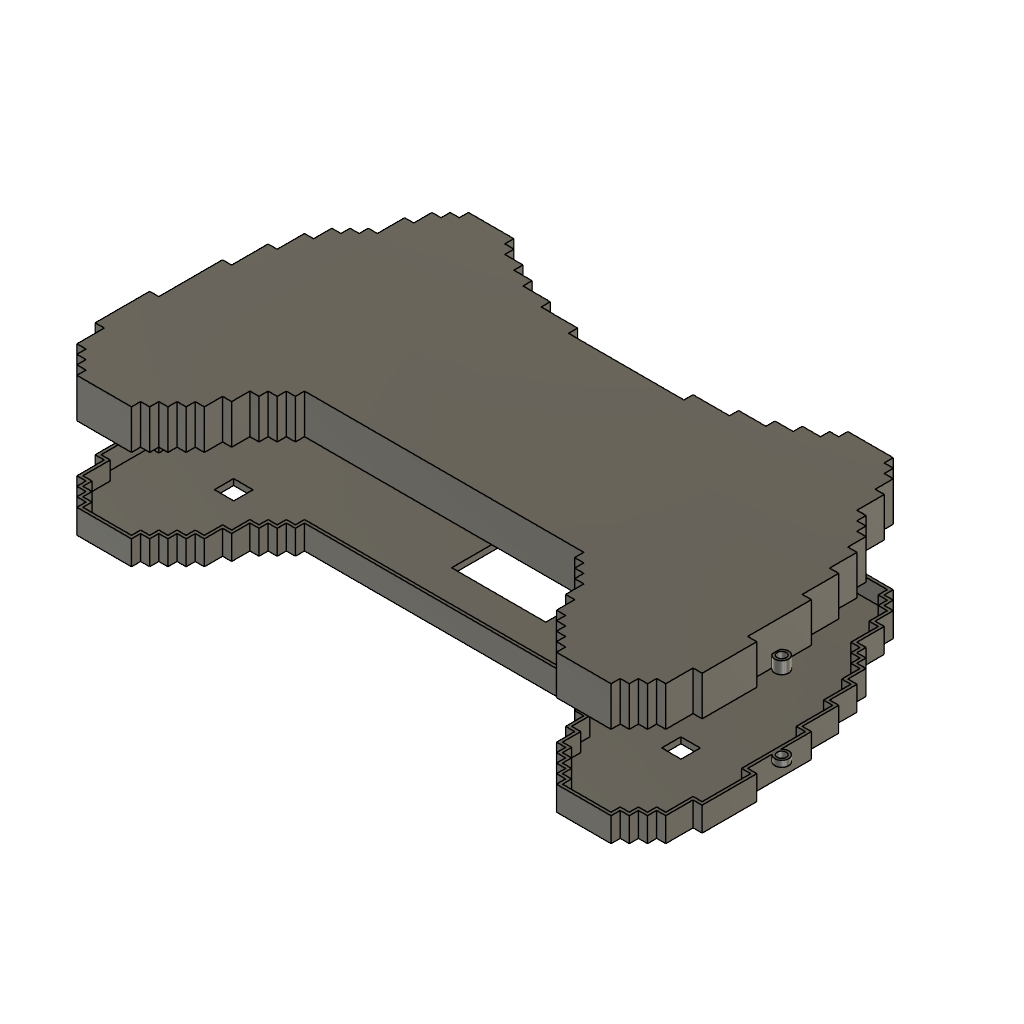
SnapPixel controller (Autodesk Fusion 360 design; units mm, degrees)
part number: 2026-10-10-15-33-20-535
Autodesk Fusion 360 part; units mm, degrees
(part 1 of 3)
sketch "Sketch1" plane through (0, 0, 0) normal (0, 0, 1) x (1, 0, 0)
sketch "Sketch2" plane through (0, 0, 0) normal (0, 0, 1) x (1, 0, 0)
  line L0 (375, 300) -> (406, 300)
  line L1 (406, 300) -> (406, 270.5)
  line L2 (406, 270.5) -> (375, 270.5)
  line L3 (375, 270.5) -> (375, 300)
  line L4 (391, 310) -> (406, 310)
  line L5 (406, 310) -> (409, 310)
  line L6 (409, 310) -> (409, 313)
  line L7 (406, 313) -> (406, 310)
  line L8 (403, 313) -> (403, 310)
  line L9 (400, 313) -> (400, 310)
  line L10 (397, 313) -> (397, 310)
  line L11 (394, 313) -> (394, 310)
  line L12 (391, 313) -> (391, 310)
  line L13 (409, 313) -> (412, 313)
  line L14 (412, 313) -> (412, 316)
  line L15 (412, 316) -> (409, 316)
  line L16 (409, 316) -> (409, 313)
  line L17 (412, 316) -> (415, 316)
  line L18 (415, 316) -> (415, 313)
  line L19 (415, 313) -> (412, 313)
  line L20 (412, 313) -> (412, 316)
  line L21 (415, 316) -> (418, 316)
  line L22 (418, 316) -> (418, 313)
  line L23 (418, 313) -> (415, 313)
  line L24 (415, 313) -> (415, 316)
  line L25 (418, 316) -> (421, 316)
  line L26 (421, 316) -> (421, 313)
  line L27 (421, 313) -> (418, 313)
  line L28 (418, 313) -> (418, 316)
  line L29 (421, 316) -> (424, 316)
  line L30 (424, 316) -> (424, 313)
  line L31 (424, 313) -> (421, 313)
  line L32 (421, 313) -> (421, 316)
  line L33 (421, 316) -> (424, 316)
  line L34 (424, 316) -> (424, 319)
  line L35 (424, 319) -> (421, 319)
  line L36 (421, 319) -> (421, 316)
  line L37 (424, 319) -> (427, 319)
  line L38 (427, 319) -> (427, 316)
  line L39 (427, 316) -> (424, 316)
  line L40 (424, 316) -> (424, 319)
  line L41 (427, 319) -> (430, 319)
  line L42 (430, 319) -> (430, 316)
  line L43 (430, 316) -> (427, 316)
  line L44 (427, 316) -> (427, 319)
  line L45 (430, 319) -> (433, 319)
  line L46 (433, 319) -> (433, 322)
  line L47 (433, 322) -> (430, 322)
  line L48 (430, 322) -> (430, 319)
  line L49 (433, 322) -> (436, 322)
  line L50 (436, 322) -> (436, 319)
  line L51 (436, 319) -> (433, 319)
  line L52 (433, 319) -> (433, 322)
  line L53 (436, 322) -> (439, 322)
  line L54 (439, 322) -> (439, 325)
  line L55 (439, 325) -> (436, 325)
  line L56 (436, 325) -> (436, 322)
  line L57 (439, 325) -> (442, 325)
  line L58 (442, 325) -> (442, 322)
  line L59 (442, 322) -> (439, 322)
  line L60 (439, 322) -> (439, 325)
  line L61 (442, 325) -> (445, 325)
  line L62 (445, 325) -> (445, 328)
  line L63 (445, 328) -> (442, 328)
  line L64 (442, 328) -> (442, 325)
  line L65 (445, 328) -> (448, 328)
  line L66 (448, 328) -> (448, 331)
  line L67 (448, 331) -> (445, 331)
  line L68 (445, 331) -> (445, 328)
  line L69 (445, 325) -> (448, 325)
  line L70 (448, 325) -> (448, 322)
  line L71 (448, 322) -> (445, 322)
  line L72 (445, 322) -> (445, 325)
  line L73 (445, 328) -> (448, 328)
  line L74 (448, 328) -> (448, 325)
  line L75 (448, 325) -> (445, 325)
  line L76 (445, 325) -> (445, 328)
  line L77 (448, 331) -> (451, 331)
  line L78 (451, 331) -> (451, 328)
  line L79 (451, 328) -> (448, 328)
  line L80 (448, 328) -> (448, 331)
  line L81 (451, 331) -> (454, 331)
  line L82 (454, 331) -> (454, 328)
  line L83 (454, 328) -> (451, 328)
  line L84 (451, 328) -> (451, 331)
  line L85 (454, 331) -> (457, 331)
  line L86 (457, 331) -> (457, 328)
  line L87 (457, 328) -> (454, 328)
  line L88 (454, 328) -> (454, 331)
  line L89 (457, 331) -> (460, 331)
  line L90 (460, 331) -> (460, 328)
  line L91 (460, 328) -> (457, 328)
  line L92 (457, 328) -> (457, 331)
  line L93 (448, 328) -> (451, 328)
  line L94 (451, 328) -> (451, 325)
  line L95 (451, 325) -> (448, 325)
  line L96 (448, 325) -> (448, 328)
  line L97 (451, 328) -> (454, 328)
  line L98 (454, 328) -> (454, 325)
  line L99 (454, 325) -> (451, 325)
  line L100 (451, 325) -> (451, 328)
  line L101 (454, 328) -> (457, 328)
  line L102 (457, 328) -> (457, 325)
  line L103 (457, 325) -> (454, 325)
  line L104 (454, 325) -> (454, 328)
  line L105 (448, 325) -> (451, 325)
  line L106 (451, 325) -> (451, 322)
  line L107 (451, 322) -> (448, 322)
  line L108 (448, 322) -> (448, 325)
  line L109 (451, 325) -> (454, 325)
  line L110 (454, 325) -> (454, 322)
  line L111 (454, 322) -> (451, 322)
  line L112 (451, 322) -> (451, 325)
  line L113 (454, 325) -> (457, 325)
  line L114 (457, 325) -> (457, 322)
  line L115 (457, 322) -> (454, 322)
  line L116 (454, 322) -> (454, 325)
  line L117 (457, 328) -> (460, 328)
  line L118 (460, 328) -> (460, 325)
  line L119 (460, 325) -> (457, 325)
  line L120 (457, 325) -> (457, 328)
  line L121 (457, 325) -> (460, 325)
  line L122 (460, 325) -> (460, 322)
  line L123 (460, 322) -> (457, 322)
  line L124 (457, 322) -> (457, 325)
  line L125 (460, 328) -> (463, 328)
  line L126 (463, 328) -> (463, 325)
  line L127 (463, 325) -> (460, 325)
  line L128 (460, 325) -> (460, 328)
  line L129 (463, 325) -> (466, 325)
  line L130 (466, 325) -> (466, 322)
  line L131 (466, 322) -> (463, 322)
  line L132 (463, 322) -> (463, 325)
  line L133 (463, 322) -> (466, 322)
  line L134 (466, 322) -> (466, 319)
  line L135 (466, 319) -> (463, 319)
  line L136 (463, 319) -> (463, 322)
  line L137 (466, 319) -> (469, 319)
  line L138 (469, 319) -> (469, 316)
  line L139 (469, 316) -> (466, 316)
  line L140 (466, 316) -> (466, 319)
  line L141 (466, 316) -> (469, 316)
  line L142 (469, 316) -> (469, 313)
  line L143 (469, 313) -> (466, 313)
  line L144 (466, 313) -> (466, 316)
  line L145 (466, 313) -> (469, 313)
  line L146 (469, 313) -> (469, 310)
  line L147 (469, 310) -> (466, 310)
  line L148 (466, 310) -> (466, 313)
  line L149 (469, 310) -> (472, 310)
  line L150 (472, 310) -> (472, 307)
  line L151 (472, 307) -> (469, 307)
  line L152 (469, 307) -> (469, 310)
  line L153 (472, 307) -> (475, 307)
  line L154 (475, 307) -> (475, 304)
  line L155 (475, 304) -> (472, 304)
  line L156 (472, 304) -> (472, 307)
  line L157 (475, 304) -> (478, 304)
  line L158 (478, 304) -> (478, 301)
  line L159 (478, 301) -> (475, 301)
  line L160 (475, 301) -> (475, 304)
  line L161 (475, 301) -> (478, 301)
  line L162 (478, 301) -> (478, 298)
  line L163 (478, 298) -> (475, 298)
  line L164 (475, 298) -> (475, 301)
  line L165 (478, 298) -> (481, 298)
  line L166 (481, 298) -> (481, 295)
  line L167 (481, 295) -> (478, 295)
  line L168 (478, 295) -> (478, 298)
  line L169 (478, 295) -> (481, 295)
  line L170 (481, 295) -> (481, 292)
  line L171 (481, 292) -> (478, 292)
  line L172 (478, 292) -> (478, 295)
  line L173 (478, 292) -> (481, 292)
  line L174 (481, 292) -> (481, 289)
  line L175 (481, 289) -> (478, 289)
  line L176 (478, 289) -> (478, 292)
  line L177 (481, 289) -> (484, 289)
  line L178 (484, 289) -> (484, 286)
  line L179 (484, 286) -> (481, 286)
  line L180 (481, 286) -> (481, 289)
  line L181 (481, 286) -> (484, 286)
  line L182 (484, 286) -> (484, 283)
  line L183 (484, 283) -> (481, 283)
  line L184 (481, 283) -> (481, 286)
  line L185 (481, 283) -> (484, 283)
  line L186 (484, 283) -> (484, 280)
  line L187 (484, 280) -> (481, 280)
  line L188 (481, 280) -> (481, 283)
  line L189 (481, 280) -> (484, 280)
  line L190 (484, 280) -> (484, 277)
  line L191 (484, 277) -> (481, 277)
  line L192 (481, 277) -> (481, 280)
  line L193 (481, 277) -> (484, 277)
  line L194 (484, 277) -> (484, 274)
  line L195 (484, 274) -> (481, 274)
  line L196 (481, 274) -> (481, 277)
  line L197 (484, 277) -> (487, 277)
  line L198 (487, 277) -> (487, 274)
  line L199 (487, 274) -> (484, 274)
  line L200 (484, 274) -> (484, 277)
  line L201 (484, 274) -> (487, 274)
  line L202 (487, 274) -> (487, 271)
  line L203 (487, 271) -> (484, 271)
  line L204 (484, 271) -> (484, 274)
  line L205 (484, 271) -> (487, 271)
  line L206 (487, 271) -> (487, 268)
  line L207 (487, 268) -> (484, 268)
  line L208 (484, 268) -> (484, 271)
  line L209 (484, 268) -> (487, 268)
  line L210 (487, 268) -> (487, 265)
  line L211 (487, 265) -> (484, 265)
  line L212 (484, 265) -> (484, 268)
  line L213 (484, 265) -> (487, 265)
  line L214 (487, 265) -> (487, 262)
  line L215 (487, 262) -> (484, 262)
  line L216 (484, 262) -> (484, 265)
  line L217 (484, 262) -> (487, 262)
  line L218 (487, 262) -> (487, 259)
  line L219 (487, 259) -> (484, 259)
  line L220 (484, 259) -> (484, 262)
  line L221 (484, 259) -> (487, 259)
  line L222 (487, 259) -> (487, 256)
  line L223 (487, 256) -> (484, 256)
  line L224 (484, 256) -> (484, 259)
  line L225 (484, 256) -> (487, 256)
  line L226 (487, 256) -> (487, 253)
  line L227 (487, 253) -> (484, 253)
  line L228 (484, 253) -> (484, 256)
  line L229 (487, 256) -> (490, 256)
  line L230 (490, 256) -> (490, 253)
  line L231 (490, 253) -> (487, 253)
  line L232 (487, 253) -> (487, 256)
  line L233 (487, 253) -> (490, 253)
  line L234 (490, 253) -> (490, 250)
  line L235 (490, 250) -> (487, 250)
  line L236 (487, 250) -> (487, 253)
  line L237 (487, 250) -> (490, 250)
  line L238 (490, 250) -> (490, 247)
  line L239 (490, 247) -> (487, 247)
  line L240 (487, 247) -> (487, 250)
  line L241 (487, 247) -> (490, 247)
  line L242 (490, 247) -> (490, 244)
  line L243 (490, 244) -> (487, 244)
  line L244 (487, 244) -> (487, 247)
  line L245 (487, 244) -> (490, 244)
  line L246 (490, 244) -> (490, 241)
  line L247 (490, 241) -> (487, 241)
  line L248 (487, 241) -> (487, 244)
  line L249 (487, 241) -> (490, 241)
  line L250 (490, 241) -> (490, 238)
  line L251 (490, 238) -> (487, 238)
  line L252 (487, 238) -> (487, 241)
  line L253 (487, 238) -> (484, 238)
  line L254 (484, 238) -> (484, 241)
  line L255 (484, 241) -> (487, 241)
  line L256 (487, 241) -> (487, 238)
  line L257 (484, 238) -> (487, 238)
  line L258 (487, 238) -> (487, 235)
  line L259 (487, 235) -> (484, 235)
  line L260 (484, 235) -> (484, 238)
  line L261 (484, 235) -> (487, 235)
  line L262 (487, 235) -> (487, 232)
  line L263 (487, 232) -> (484, 232)
  line L264 (484, 232) -> (484, 235)
  line L265 (484, 232) -> (487, 232)
  line L266 (487, 232) -> (487, 229)
  line L267 (487, 229) -> (484, 229)
  line L268 (484, 229) -> (484, 232)
  line L269 (484, 232) -> (481, 232)
  line L270 (481, 232) -> (481, 229)
  line L271 (481, 229) -> (484, 229)
  line L272 (484, 229) -> (484, 232)
  line L273 (481, 229) -> (484, 229)
  line L274 (484, 229) -> (484, 226)
  line L275 (484, 226) -> (481, 226)
  line L276 (481, 226) -> (481, 229)
  line L277 (478, 229) -> (481, 229)
  line L278 (481, 229) -> (481, 226)
  line L279 (481, 226) -> (478, 226)
  line L280 (478, 226) -> (478, 229)
  line L281 (478, 226) -> (481, 226)
  line L282 (481, 226) -> (481, 223)
  line L283 (481, 223) -> (478, 223)
  line L284 (478, 223) -> (478, 226)
  line L285 (478, 223) -> (475, 223)
  line L286 (475, 223) -> (475, 220)
  line L287 (475, 220) -> (478, 220)
  line L288 (478, 220) -> (478, 223)
  line L289 (475, 223) -> (472, 223)
  line L290 (472, 223) -> (472, 220)
  line L291 (472, 220) -> (475, 220)
  line L292 (475, 220) -> (475, 223)
  line L293 (472, 223) -> (469, 223)
  line L294 (469, 223) -> (469, 220)
  line L295 (469, 220) -> (472, 220)
  line L296 (472, 220) -> (472, 223)
  line L297 (469, 223) -> (466, 223)
  line L298 (466, 223) -> (466, 220)
  line L299 (466, 220) -> (469, 220)
  line L300 (469, 220) -> (469, 223)
  line L301 (466, 223) -> (463, 223)
  line L302 (463, 223) -> (463, 220)
  line L303 (463, 220) -> (466, 220)
  line L304 (466, 220) -> (466, 223)
  line L305 (463, 223) -> (460, 223)
  line L306 (460, 223) -> (460, 220)
  line L307 (460, 220) -> (463, 220)
  line L308 (463, 220) -> (463, 223)
  line L309 (460, 226) -> (463, 226)
  line L310 (463, 226) -> (463, 223)
  line L311 (463, 223) -> (460, 223)
  line L312 (460, 223) -> (460, 226)
  line L313 (460, 226) -> (457, 226)
  line L314 (457, 226) -> (457, 223)
  line L315 (457, 223) -> (460, 223)
  line L316 (460, 223) -> (460, 226)
  line L317 (457, 226) -> (454, 226)
  line L318 (454, 226) -> (454, 229)
  line L319 (454, 229) -> (457, 229)
  line L320 (457, 229) -> (457, 226)
  line L321 (454, 229) -> (451, 229)
  line L322 (451, 229) -> (451, 232)
  line L323 (451, 232) -> (454, 232)
  line L324 (454, 232) -> (454, 229)
  line L325 (451, 232) -> (454, 232)
  line L326 (454, 232) -> (454, 235)
  line L327 (454, 235) -> (451, 235)
  line L328 (451, 235) -> (451, 232)
  line L329 (451, 235) -> (448, 235)
  line L330 (448, 235) -> (448, 232)
  line L331 (448, 232) -> (451, 232)
  line L332 (451, 232) -> (451, 235)
  line L333 (448, 235) -> (451, 235)
  line L334 (451, 235) -> (451, 238)
  line L335 (451, 238) -> (448, 238)
  line L336 (448, 238) -> (448, 235)
  line L337 (448, 238) -> (445, 238)
  line L338 (445, 238) -> (445, 241)
  line L339 (445, 241) -> (448, 241)
  line L340 (448, 241) -> (448, 238)
  line L341 (448, 241) -> (445, 241)
  line L342 (445, 241) -> (445, 244)
  line L343 (445, 244) -> (448, 244)
  line L344 (448, 244) -> (448, 241)
  line L345 (448, 244) -> (445, 244)
  line L346 (445, 244) -> (445, 247)
  line L347 (445, 247) -> (448, 247)
  line L348 (448, 247) -> (448, 244)
  line L349 (445, 247) -> (442, 247)
  line L350 (442, 247) -> (442, 244)
  line L351 (442, 244) -> (445, 244)
  line L352 (445, 244) -> (445, 247)
  line L353 (445, 247) -> (442, 247)
  line L354 (442, 247) -> (442, 250)
  line L355 (442, 250) -> (445, 250)
  line L356 (445, 250) -> (445, 247)
  line L357 (442, 250) -> (439, 250)
  line L358 (439, 250) -> (439, 247)
  line L359 (439, 247) -> (442, 247)
  line L360 (442, 247) -> (442, 250)
  line L361 (439, 250) -> (436, 250)
  line L362 (436, 250) -> (436, 253)
  line L363 (436, 253) -> (439, 253)
  line L364 (439, 253) -> (439, 250)
  line L365 (436, 253) -> (433, 253)
  line L366 (433, 253) -> (433, 256)
  line L367 (433, 256) -> (436, 256)
  line L368 (436, 256) -> (436, 253)
  line L369 (433, 256) -> (389.9479, 256)
  line L370 (389.9479, 256) -> (389.9479, 253)
  line L371 (389.9479, 253) -> (433, 253)
  line L372 (433, 253) -> (433, 256)
  line L373 (390, 340) -> (390, 200) construction
  line L374 (317, 322) -> (314, 322)
  line L375 (329, 325) -> (329, 328)
  line L376 (323, 322) -> (326, 322)
  line L377 (323, 328) -> (326, 328)
  line L378 (311, 319) -> (311, 316)
  line L379 (326, 322) -> (329, 322)
  line L380 (326, 331) -> (326, 328)
  line L381 (311, 310) -> (314, 310)
  line L382 (320, 325) -> (320, 328)
  line L383 (314, 319) -> (311, 319)
  line L384 (326, 328) -> (326, 325)
  line L385 (320, 328) -> (320, 325)
  line L386 (311, 310) -> (308, 310)
  line L387 (329, 322) -> (329, 325)
  line L388 (311, 313) -> (314, 313)
  line L389 (317, 325) -> (320, 325)
  line L390 (317, 319) -> (317, 322)
  line L391 (320, 325) -> (320, 322)
  line L392 (326, 328) -> (326, 331)
  line L393 (326, 328) -> (323, 328)
  line L394 (314, 313) -> (311, 313)
  line L395 (329, 331) -> (329, 328)
  line L396 (314, 316) -> (314, 319)
  line L397 (314, 316) -> (311, 316)
  line L398 (329, 328) -> (326, 328)
  line L399 (317, 328) -> (317, 325)
  line L400 (323, 328) -> (323, 325)
  line L401 (329, 325) -> (329, 322)
  line L402 (323, 325) -> (323, 322)
  line L403 (332, 328) -> (332, 331)
  line L404 (338, 322) -> (341, 322)
  line L405 (326, 325) -> (326, 328)
  line L406 (329, 328) -> (329, 331)
  line L407 (332, 322) -> (332, 325)
  line L408 (311, 316) -> (314, 316)
  line L409 (314, 310) -> (314, 313)
  line L410 (326, 322) -> (326, 325)
  line L411 (326, 328) -> (329, 328)
  line L412 (323, 325) -> (323, 328)
  line L413 (320, 328) -> (317, 328)
  line L414 (314, 322) -> (317, 322)
  line L415 (335, 322) -> (335, 325)
  line L416 (323, 331) -> (323, 328)
  line L417 (326, 331) -> (323, 331)
  line L418 (311, 313) -> (311, 310)
  line L419 (335, 328) -> (332, 328)
  line L420 (350, 319) -> (347, 319)
  line L421 (326, 325) -> (323, 325)
  line L422 (317, 325) -> (314, 325)
  line L423 (335, 325) -> (335, 328)
  line L424 (335, 328) -> (332, 328)
  line L425 (341, 325) -> (338, 325)
  line L426 (332, 325) -> (335, 325)
  line L427 (320, 331) -> (320, 328)
  line L428 (341, 322) -> (341, 325)
  line L429 (332, 325) -> (332, 322)
  line L430 (314, 325) -> (314, 322)
  line L431 (326, 325) -> (326, 322)
  line L432 (335, 325) -> (335, 328)
  line L433 (314, 319) -> (317, 319)
  line L434 (323, 322) -> (323, 325)
  line L435 (335, 325) -> (332, 325)
  line L436 (383, 313) -> (383, 310)
  line L437 (359, 316) -> (356, 316)
  line L438 (374, 313) -> (374, 310)
  line L439 (344, 322) -> (341, 322)
  line L440 (359, 313) -> (359, 316)
  line L441 (341, 325) -> (344, 325)
  line L442 (362, 316) -> (359, 316)
  line L443 (368, 316) -> (371, 316)
  line L444 (368, 313) -> (368, 316)
  line L445 (365, 316) -> (362, 316)
  line L446 (347, 322) -> (344, 322)
  line L447 (329, 322) -> (332, 322)
  line L448 (332, 331) -> (329, 331)
  line L449 (356, 316) -> (356, 319)
  line L450 (332, 325) -> (329, 325)
  line L451 (329, 328) -> (332, 328)
  line L452 (356, 316) -> (356, 319)
  line L453 (356, 319) -> (353, 319)
  line L454 (362, 313) -> (362, 316)
  line L455 (323, 328) -> (320, 328)
  line L456 (347, 319) -> (347, 322)
  line L457 (323, 331) -> (320, 331)
  line L458 (356, 316) -> (356, 313)
  line L459 (359, 313) -> (362, 313)
  line L460 (320, 325) -> (323, 325)
  line L461 (320, 322) -> (323, 322)
  line L462 (332, 328) -> (329, 328)
  line L463 (368, 313) -> (368, 316)
  line L464 (371, 313) -> (368, 313)
  line L465 (365, 316) -> (365, 313)
  line L466 (365, 313) -> (368, 313)
  line L467 (368, 316) -> (365, 316)
  line L468 (371, 310) -> (371, 313)
  line L469 (338, 325) -> (335, 325)
  line L470 (320, 328) -> (323, 328)
  line L471 (353, 319) -> (353, 316)
  line L472 (329, 325) -> (332, 325)
  line L473 (362, 313) -> (365, 313)
  line L474 (332, 328) -> (332, 331)
  line L475 (359, 319) -> (359, 316)
  line L476 (353, 319) -> (350, 319)
  line L477 (344, 325) -> (344, 322)
  line L478 (359, 316) -> (359, 313)
  line L479 (332, 325) -> (332, 328)
  line L480 (323, 325) -> (320, 325)
  line L481 (338, 328) -> (338, 325)
  line L482 (362, 316) -> (362, 313)
  line L483 (365, 313) -> (365, 316)
  line L484 (350, 322) -> (350, 319)
  line L485 (314, 313) -> (314, 316)
  line L486 (353, 316) -> (353, 319)
  line L487 (347, 322) -> (350, 322)
  line L488 (332, 322) -> (335, 322)
  line L489 (311, 307) -> (311, 310)
  line L490 (326, 325) -> (329, 325)
  line L491 (323, 325) -> (326, 325)
  line L492 (350, 316) -> (353, 316)
  line L493 (371, 316) -> (371, 313)
  line L494 (344, 322) -> (344, 319)
  line L495 (350, 319) -> (350, 316)
  line L496 (308, 310) -> (308, 307)
  line L497 (329, 325) -> (326, 325)
  line L498 (353, 316) -> (356, 316)
  line L499 (332, 328) -> (332, 325)
  line L500 (338, 325) -> (338, 322)
  line L501 (335, 328) -> (338, 328)
  line L502 (335, 331) -> (335, 328)
  line L503 (329, 331) -> (326, 331)
  line L504 (341, 322) -> (341, 325)
  line L505 (344, 319) -> (347, 319)
  line L506 (332, 331) -> (335, 331)
  line L507 (311, 316) -> (311, 313)
  line L508 (317, 322) -> (317, 325)
  line L509 (347, 319) -> (347, 322)
  line L510 (329, 328) -> (329, 325)
  line L511 (314, 322) -> (314, 319)
  line L512 (323, 328) -> (323, 331)
  line L513 (356, 319) -> (359, 319)
  line L514 (374, 310) -> (371, 310)
  line L515 (380, 313) -> (380, 310)
  line L516 (356, 313) -> (359, 313)
  line L517 (386, 313) -> (386, 310)
  line L518 (389, 313) -> (389, 310)
  line L519 (377, 313) -> (377, 310)
  line L520 (359, 316) -> (356, 316)
  line L521 (389, 310) -> (374, 310)
  line L522 (293, 271) -> (293, 268)
  line L523 (308, 223) -> (311, 223)
  line L524 (296, 286) -> (296, 283)
  line L525 (311, 220) -> (308, 220)
  line L526 (299, 283) -> (299, 286)
  line L527 (299, 280) -> (296, 280)
  line L528 (290, 256) -> (290, 253)
  line L529 (293, 244) -> (293, 247)
  line L530 (293, 247) -> (293, 250)
  line L531 (293, 241) -> (290, 241)
  line L532 (293, 253) -> (293, 256)
  line L533 (296, 253) -> (296, 256)
  line L534 (290, 241) -> (293, 241)
  line L535 (302, 295) -> (299, 295)
  line L536 (293, 247) -> (290, 247)
  line L537 (299, 277) -> (299, 280)
  line L538 (293, 244) -> (290, 244)
  line L539 (296, 280) -> (296, 277)
  line L540 (293, 256) -> (293, 253)
  line L541 (296, 271) -> (293, 271)
  line L542 (290, 247) -> (290, 244)
  line L543 (296, 277) -> (293, 277)
  line L544 (299, 289) -> (302, 289)
  line L545 (302, 292) -> (299, 292)
  line L546 (296, 262) -> (296, 265)
  line L547 (293, 274) -> (296, 274)
  line L548 (302, 292) -> (302, 295)
  line L549 (299, 283) -> (296, 283)
  line L550 (311, 223) -> (311, 220)
  line L551 (296, 274) -> (296, 277)
  line L552 (293, 250) -> (290, 250)
  line L553 (290, 250) -> (293, 250)
  line L554 (293, 238) -> (293, 241)
  line L555 (311, 220) -> (311, 223)
  line L556 (293, 262) -> (296, 262)
  line L557 (299, 286) -> (296, 286)
  line L558 (296, 280) -> (299, 280)
  line L559 (299, 280) -> (299, 283)
  line L560 (296, 238) -> (296, 241)
  line L561 (299, 277) -> (296, 277)
  line L562 (290, 244) -> (293, 244)
  line L563 (290, 241) -> (290, 238)
  line L564 (290, 253) -> (290, 250)
  line L565 (299, 295) -> (299, 292)
  line L566 (299, 292) -> (299, 289)
  line L567 (296, 271) -> (296, 274)
  line L568 (296, 277) -> (299, 277)
  line L569 (314, 220) -> (311, 220)
  line L570 (296, 268) -> (293, 268)
  line L571 (293, 256) -> (290, 256)
  line L572 (305, 298) -> (305, 301)
  line L573 (302, 289) -> (302, 292)
  line L574 (293, 265) -> (293, 262)
  line L575 (290, 253) -> (293, 253)
  line L576 (293, 268) -> (293, 265)
  line L577 (293, 274) -> (293, 271)
  line L578 (296, 256) -> (293, 256)
  line L579 (299, 295) -> (302, 295)
  line L580 (293, 256) -> (296, 256)
  line L581 (296, 283) -> (299, 283)
  line L582 (293, 241) -> (293, 244)
  line L583 (293, 271) -> (296, 271)
  line L584 (311, 223) -> (314, 223)
  line L585 (296, 259) -> (296, 262)
  line L586 (296, 259) -> (293, 259)
  line L587 (293, 241) -> (293, 238)
  line L588 (296, 274) -> (299, 274)
  line L589 (293, 259) -> (293, 256)
  line L590 (299, 274) -> (299, 277)
  line L591 (293, 262) -> (293, 259)
  line L592 (296, 265) -> (296, 268)
  line L593 (293, 277) -> (293, 274)
  line L594 (296, 274) -> (293, 274)
  line L595 (296, 283) -> (296, 280)
  line L596 (296, 241) -> (293, 241)
  line L597 (293, 250) -> (293, 253)
  line L598 (296, 265) -> (293, 265)
  line L599 (299, 289) -> (296, 289)
  line L600 (299, 298) -> (299, 295)
  line L601 (293, 253) -> (290, 253)
  line L602 (293, 259) -> (296, 259)
  line L603 (302, 304) -> (302, 301)
  line L604 (302, 295) -> (302, 298)
  line L605 (293, 268) -> (296, 268)
  line L606 (290, 244) -> (290, 241)
  line L607 (302, 298) -> (305, 298)
  line L608 (296, 238) -> (293, 238)
  line L609 (296, 277) -> (296, 274)
  line L610 (305, 301) -> (302, 301)
  line L611 (299, 229) -> (296, 229)
  line L612 (293, 253) -> (296, 253)
  line L613 (302, 298) -> (299, 298)
  line L614 (296, 256) -> (296, 259)
  line L615 (299, 292) -> (302, 292)
  line L616 (296, 262) -> (293, 262)
  line L617 (299, 226) -> (299, 229)
  line L618 (290, 247) -> (293, 247)
  line L619 (293, 265) -> (296, 265)
  line L620 (296, 286) -> (299, 286)
  line L621 (302, 301) -> (302, 298)
  line L622 (296, 268) -> (296, 271)
  line L623 (290, 250) -> (290, 247)
  line L624 (296, 289) -> (296, 286)
  line L625 (296, 229) -> (296, 226)
  line L626 (308, 220) -> (305, 220)
  line L627 (299, 232) -> (299, 229)
  line L628 (296, 232) -> (293, 232)
  line L629 (299, 226) -> (299, 223)
  line L630 (293, 238) -> (296, 238)
  line L631 (305, 220) -> (305, 223)
  line L632 (299, 226) -> (302, 226)
  line L633 (302, 301) -> (305, 301)
  line L634 (299, 286) -> (299, 289)
  line L635 (299, 229) -> (299, 226)
  line L636 (293, 238) -> (293, 235)
  line L637 (290, 238) -> (293, 238)
  line L638 (305, 223) -> (308, 223)
  line L639 (305, 301) -> (305, 304)
  line L640 (293, 229) -> (296, 229)
  line L641 (302, 220) -> (302, 223)
  line L642 (293, 232) -> (293, 229)
  line L643 (296, 229) -> (296, 232)
  line L644 (296, 229) -> (296, 232)
  line L645 (302, 229) -> (299, 229)
  line L646 (296, 232) -> (296, 235)
  line L647 (299, 229) -> (296, 229)
  line L648 (302, 226) -> (302, 229)
  line L649 (305, 223) -> (305, 220)
  line L650 (305, 220) -> (302, 220)
  line L651 (302, 226) -> (299, 226)
  line L652 (296, 235) -> (293, 235)
  line L653 (308, 223) -> (308, 220)
  line L654 (293, 235) -> (293, 232)
  line L655 (302, 223) -> (302, 226)
  line L656 (296, 232) -> (299, 232)
  line L657 (308, 220) -> (308, 223)
  line L658 (296, 226) -> (299, 226)
  line L659 (293, 235) -> (296, 235)
  line L660 (293, 232) -> (296, 232)
  line L661 (299, 223) -> (302, 223)
  line L662 (296, 235) -> (296, 238)
  line L663 (302, 223) -> (305, 223)
  line L664 (347, 253) -> (347, 256)
  line L665 (347, 253) -> (347, 256)
  line L666 (326, 229) -> (323, 229)
  line L667 (320, 226) -> (317, 226)
  line L668 (326, 229) -> (329, 229)
  line L669 (338, 244) -> (335, 244)
  line L670 (341, 253) -> (341, 250)
  line L671 (320, 226) -> (323, 226)
  line L672 (335, 247) -> (338, 247)
  line L673 (338, 247) -> (338, 244)
  line L674 (344, 253) -> (341, 253)
  line L675 (338, 250) -> (341, 250)
  line L676 (326, 226) -> (326, 229)
  line L677 (335, 247) -> (338, 247)
  line L678 (326, 232) -> (326, 229)
  line L679 (329, 229) -> (329, 232)
  line L680 (338, 247) -> (338, 250)
  line L681 (323, 226) -> (326, 226)
  line L682 (341, 247) -> (338, 247)
  line L683 (323, 229) -> (323, 226)
  line L684 (341, 250) -> (341, 247)
  line L685 (338, 247) -> (338, 250)
  line L686 (341, 250) -> (344, 250)
  line L687 (338, 250) -> (335, 250)
  line L688 (344, 250) -> (344, 253)
  line L689 (344, 256) -> (344, 253)
  line L690 (344, 253) -> (347, 253)
  line L691 (347, 256) -> (344, 256)
  line L692 (390.0521, 256) -> (390.0521, 253)
  line L693 (390.0521, 253) -> (347, 253)
  line L694 (347, 256) -> (390.0521, 256)
  line L695 (317, 220) -> (314, 220)
  line L696 (329, 229) -> (329, 232)
  line L697 (311, 223) -> (311, 220)
  line L698 (317, 223) -> (320, 223)
  line L699 (329, 232) -> (326, 232)
  line L700 (311, 223) -> (314, 223)
  line L701 (338, 250) -> (341, 250)
  line L702 (329, 232) -> (329, 235)
  line L703 (320, 223) -> (320, 226)
  line L704 (335, 244) -> (335, 247)
  line L705 (329, 232) -> (326, 232)
  line L706 (326, 229) -> (329, 229)
  line L707 (320, 223) -> (320, 226)
  line L708 (341, 250) -> (341, 247)
  line L709 (332, 244) -> (335, 244)
  line L710 (332, 241) -> (332, 238)
  line L711 (335, 244) -> (335, 247)
  line L712 (317, 223) -> (320, 223)
  line L713 (335, 247) -> (338, 247)
  line L714 (332, 238) -> (335, 238)
  line L715 (314, 220) -> (311, 220)
  line L716 (314, 220) -> (314, 223)
  line L717 (326, 235) -> (329, 235)
  line L718 (335, 244) -> (332, 244)
  line L719 (320, 220) -> (317, 220)
  line L720 (329, 235) -> (332, 235)
  line L721 (332, 232) -> (329, 232)
  line L722 (311, 220) -> (311, 223)
  line L723 (326, 229) -> (323, 229)
  line L724 (329, 235) -> (329, 232)
  line L725 (314, 223) -> (317, 223)
  line L726 (332, 247) -> (332, 244)
  line L727 (326, 232) -> (326, 229)
  line L728 (323, 226) -> (323, 223)
  line L729 (326, 232) -> (326, 235)
  line L730 (335, 250) -> (335, 247)
  line L731 (308, 220) -> (308, 223)
  line L732 (332, 244) -> (332, 241)
  line L733 (323, 226) -> (326, 226)
  line L734 (335, 241) -> (332, 241)
  line L735 (338, 247) -> (338, 250)
  line L736 (308, 223) -> (308, 220)
  line L737 (332, 235) -> (329, 235)
  line L738 (323, 229) -> (323, 226)
  line L739 (338, 247) -> (338, 250)
  line L740 (335, 241) -> (335, 244)
  line L741 (344, 253) -> (341, 253)
  line L742 (332, 235) -> (332, 232)
  line L743 (335, 238) -> (335, 241)
  line L744 (329, 238) -> (332, 238)
  line L745 (341, 253) -> (341, 250)
  line L746 (338, 247) -> (338, 244)
  line L747 (338, 250) -> (335, 250)
  line L748 (335, 247) -> (332, 247)
  line L749 (341, 250) -> (344, 250)
  line L750 (332, 241) -> (335, 241)
  line L751 (335, 247) -> (338, 247)
  line L752 (326, 226) -> (326, 229)
  line L753 (338, 244) -> (335, 244)
  line L754 (341, 247) -> (338, 247)
  line L755 (308, 223) -> (311, 223)
  line L756 (311, 220) -> (308, 220)
  line L757 (314, 223) -> (314, 220)
  line L758 (317, 226) -> (317, 223)
  line L759 (332, 238) -> (332, 235)
  line L760 (320, 223) -> (320, 220)
  line L761 (320, 226) -> (317, 226)
  line L762 (320, 226) -> (323, 226)
  line L763 (329, 235) -> (329, 238)
  line L764 (317, 220) -> (317, 223)
  line L765 (323, 223) -> (320, 223)
  line L766 (317, 223) -> (317, 220)
  line L767 (305, 307) -> (311, 307)
  line L768 (305, 307) -> (305, 304)
  line L769 (302, 304) -> (305, 304)
  line L770 (305, 304) -> (308, 304)
  line L771 (308, 304) -> (308, 307)
  line L772 (371, 313) -> (389, 313)
  line L773 (389, 313) -> (391, 313)
  line L774 (391, 313) -> (409, 313)
  point P0 (305, 307)
  point P1 (314, 220)
  dimension "d1" = 29.5
  dimension "d2" = 31
  dimension "d3" = 18
  constraint horizontal L0
  constraint vertical L1
  constraint horizontal L2
  constraint vertical L3
  constraint perpendicular L5 L6
  constraint perpendicular L5 L7
  constraint coincident L4 L8.end
  constraint perpendicular L4 L8
  constraint coincident L4 L9.end
  constraint perpendicular L4 L9
  constraint coincident L4 L10.end
  constraint perpendicular L4 L10
  constraint coincident L4 L11.end
  constraint perpendicular L4 L11
  constraint coincident L4 L12.end
  constraint perpendicular L4 L12
  constraint horizontal L13
  constraint vertical L14
  constraint horizontal L15
  constraint vertical L16
  constraint horizontal L17
  constraint vertical L18
  constraint horizontal L19
  constraint vertical L20
  constraint horizontal L21
  constraint vertical L22
  constraint horizontal L23
  constraint vertical L24
  constraint horizontal L25
  constraint vertical L26
  constraint horizontal L27
  constraint vertical L28
  constraint horizontal L29
  constraint vertical L30
  constraint horizontal L31
  constraint vertical L32
  constraint horizontal L33
  constraint vertical L34
  constraint horizontal L35
  constraint vertical L36
  constraint horizontal L37
  constraint vertical L38
  constraint horizontal L39
  constraint vertical L40
  constraint horizontal L41
  constraint vertical L42
  constraint horizontal L43
  constraint vertical L44
  constraint horizontal L45
  constraint vertical L46
  constraint horizontal L47
  constraint vertical L48
  constraint horizontal L49
  constraint vertical L50
  constraint horizontal L51
  constraint vertical L52
  constraint horizontal L53
  constraint vertical L54
  constraint horizontal L55
  constraint vertical L56
  constraint horizontal L57
  constraint vertical L58
  constraint horizontal L59
  constraint vertical L60
  constraint horizontal L61
  constraint vertical L62
  constraint horizontal L63
  constraint vertical L64
  constraint horizontal L65
  constraint vertical L66
  constraint horizontal L67
  constraint vertical L68
  constraint horizontal L69
  constraint vertical L70
  constraint horizontal L71
  constraint vertical L72
  constraint horizontal L73
  constraint vertical L74
  constraint horizontal L75
  constraint vertical L76
  constraint horizontal L77
  constraint vertical L78
  constraint horizontal L79
  constraint vertical L80
  constraint horizontal L81
  constraint vertical L82
  constraint horizontal L83
  constraint vertical L84
  constraint horizontal L85
  constraint vertical L86
  constraint horizontal L87
  constraint vertical L88
  constraint horizontal L89
  constraint vertical L90
  constraint horizontal L91
  constraint vertical L92
  constraint horizontal L93
  constraint vertical L94
  constraint horizontal L95
  constraint vertical L96
  constraint horizontal L97
  constraint vertical L98
  constraint horizontal L99
  constraint vertical L100
  constraint horizontal L101
  constraint vertical L102
  constraint horizontal L103
  constraint vertical L104
  constraint horizontal L105
  constraint vertical L106
  constraint horizontal L107
  constraint vertical L108
  constraint horizontal L109
  constraint vertical L110
  constraint horizontal L111
  constraint vertical L112
  constraint horizontal L113
  constraint vertical L114
  constraint horizontal L115
  constraint vertical L116
  constraint horizontal L117
  constraint vertical L118
  constraint horizontal L119
  constraint vertical L120
  constraint horizontal L121
  constraint vertical L122
  constraint horizontal L123
  constraint vertical L124
  constraint horizontal L125
  constraint vertical L126
  constraint horizontal L127
  constraint vertical L128
  constraint horizontal L129
  constraint vertical L130
  constraint horizontal L131
  constraint vertical L132
  constraint horizontal L133
  constraint vertical L134
  constraint horizontal L135
  constraint vertical L136
  constraint horizontal L137
  constraint vertical L138
  constraint horizontal L139
  constraint vertical L140
  constraint horizontal L141
  constraint vertical L142
  constraint horizontal L143
  constraint vertical L144
  constraint horizontal L145
  constraint vertical L146
  constraint horizontal L147
  constraint vertical L148
  constraint horizontal L149
  constraint vertical L150
  constraint horizontal L151
  constraint vertical L152
  constraint horizontal L153
  constraint vertical L154
  constraint horizontal L155
  constraint vertical L156
  constraint horizontal L157
  constraint vertical L158
  constraint horizontal L159
  constraint vertical L160
  constraint horizontal L161
  constraint vertical L162
  constraint horizontal L163
  constraint vertical L164
  constraint horizontal L165
  constraint vertical L166
  constraint horizontal L167
  constraint vertical L168
  constraint horizontal L169
  constraint vertical L170
  constraint horizontal L171
  constraint vertical L172
  constraint horizontal L173
  constraint vertical L174
  constraint horizontal L175
  constraint vertical L176
  constraint horizontal L177
  constraint vertical L178
  constraint horizontal L179
  constraint vertical L180
  constraint horizontal L181
  constraint vertical L182
  constraint horizontal L183
  constraint vertical L184
  constraint horizontal L185
  constraint vertical L186
  constraint horizontal L187
  constraint vertical L188
  constraint horizontal L189
  constraint vertical L190
  constraint horizontal L191
  constraint vertical L192
  constraint horizontal L193
  constraint vertical L194
  constraint horizontal L195
  constraint vertical L196
  constraint horizontal L197
  constraint vertical L198
  constraint horizontal L199
  constraint vertical L200
  constraint horizontal L201
  constraint vertical L202
  constraint horizontal L203
  constraint vertical L204
  constraint horizontal L205
  constraint vertical L206
  constraint horizontal L207
  constraint vertical L208
  constraint horizontal L209
  constraint vertical L210
  constraint horizontal L211
  constraint vertical L212
  constraint horizontal L213
  constraint vertical L214
  constraint horizontal L215
  constraint vertical L216
  constraint horizontal L217
  constraint vertical L218
  constraint horizontal L219
  constraint vertical L220
  constraint horizontal L221
  constraint vertical L222
  constraint horizontal L223
  constraint vertical L224
  constraint horizontal L225
  constraint vertical L226
  constraint horizontal L227
  constraint vertical L228
  constraint horizontal L229
  constraint vertical L230
  constraint horizontal L231
  constraint vertical L232
  constraint horizontal L233
  constraint vertical L234
  constraint horizontal L235
  constraint vertical L236
  constraint horizontal L237
  constraint vertical L238
  constraint horizontal L239
  constraint vertical L240
  constraint horizontal L241
  constraint vertical L242
  constraint horizontal L243
  constraint vertical L244
  constraint horizontal L245
  constraint vertical L246
  constraint horizontal L247
  constraint vertical L248
  constraint horizontal L249
  constraint vertical L250
  constraint horizontal L251
  constraint vertical L252
  constraint horizontal L253
  constraint vertical L254
  constraint horizontal L255
  constraint vertical L256
  constraint horizontal L257
  constraint vertical L258
  constraint horizontal L259
  constraint vertical L260
  constraint horizontal L261
  constraint vertical L262
  constraint horizontal L263
  constraint vertical L264
  constraint horizontal L265
  constraint vertical L266
  constraint horizontal L267
  constraint vertical L268
  constraint horizontal L269
  constraint vertical L270
  constraint horizontal L271
  constraint vertical L272
  constraint horizontal L273
  constraint vertical L274
  constraint horizontal L275
  constraint vertical L276
  constraint horizontal L277
  constraint vertical L278
  constraint horizontal L279
  constraint vertical L280
  constraint horizontal L281
  constraint vertical L282
  constraint horizontal L283
  constraint vertical L284
  constraint horizontal L285
  constraint vertical L286
  constraint horizontal L287
  constraint vertical L288
  constraint horizontal L289
  constraint vertical L290
  constraint horizontal L291
  constraint vertical L292
  constraint horizontal L293
  constraint vertical L294
  constraint horizontal L295
  constraint vertical L296
  constraint horizontal L297
  constraint vertical L298
  constraint horizontal L299
  constraint vertical L300
  constraint horizontal L301
  constraint vertical L302
  constraint horizontal L303
  constraint vertical L304
  constraint horizontal L305
  constraint vertical L306
  constraint horizontal L307
  constraint vertical L308
  constraint horizontal L309
  constraint vertical L310
  constraint horizontal L311
  constraint vertical L312
  constraint horizontal L313
  constraint vertical L314
  constraint horizontal L315
  constraint vertical L316
  constraint horizontal L317
  constraint vertical L318
  constraint horizontal L319
  constraint vertical L320
  constraint horizontal L321
  constraint vertical L322
  constraint horizontal L323
  constraint vertical L324
  constraint horizontal L325
  constraint vertical L326
  constraint horizontal L327
  constraint vertical L328
  constraint horizontal L329
  constraint vertical L330
  constraint horizontal L331
  constraint vertical L332
  constraint horizontal L333
  constraint vertical L334
  constraint horizontal L335
  constraint vertical L336
  constraint horizontal L337
  constraint vertical L338
  constraint horizontal L339
  constraint vertical L340
  constraint horizontal L341
  constraint vertical L342
  constraint horizontal L343
  constraint vertical L344
  constraint horizontal L345
  constraint vertical L346
  constraint horizontal L347
  constraint vertical L348
  constraint horizontal L349
  constraint vertical L350
  constraint horizontal L351
  constraint vertical L352
  constraint horizontal L353
  constraint vertical L354
  constraint horizontal L355
  constraint vertical L356
  constraint horizontal L357
  constraint vertical L358
  constraint horizontal L359
  constraint vertical L360
  constraint horizontal L361
  constraint vertical L362
  constraint horizontal L363
  constraint vertical L364
  constraint horizontal L365
  constraint vertical L366
  constraint horizontal L367
  constraint vertical L368
  constraint horizontal L369
  constraint vertical L370
  constraint horizontal L371
  constraint vertical L372
  constraint perpendicular L2 L373
  constraint symmetric L4.start L373 L518.end
  constraint symmetric L4.end L373 L438.end
  constraint symmetric L5.end L373 L468.start
  constraint symmetric L6.end L373 L464.start
  constraint symmetric L7.start L373 L438.start
  constraint symmetric L8.start L373 L519.start
  constraint symmetric L8.end L373 L519.end
  constraint symmetric L9.start L373 L515.start
  constraint symmetric L9.end L373 L515.end
  constraint symmetric L10.start L373 L436.start
  constraint symmetric L10.end L373 L436.end
  constraint symmetric L11.start L373 L517.start
  constraint symmetric L11.end L373 L517.end
  constraint symmetric L12.start L373 L518.start
  constraint symmetric L13.end L373 L444.start
  constraint symmetric L14.end L373 L443.start
  constraint symmetric L15.end L373 L443.end
  constraint symmetric L17.end L373 L445.start
  constraint symmetric L18.end L373 L465.end
  constraint symmetric L21.end L373 L442.start
  constraint symmetric L22.end L373 L454.start
  constraint symmetric L25.end L373 L437.start
  constraint symmetric L26.end L373 L440.start
  constraint symmetric L29.end L373 L437.end
  constraint symmetric L30.end L373 L458.end
  constraint symmetric L34.end L373 L449.end
  constraint symmetric L35.end L373 L475.start
  constraint symmetric L37.end L373 L453.end
  constraint symmetric L38.end L373 L471.end
  constraint symmetric L41.end L373 L420.start
  constraint symmetric L42.end L373 L492.start
  constraint symmetric L45.end L373 L420.end
  constraint symmetric L46.end L373 L446.start
  constraint symmetric L47.end L373 L484.start
  constraint symmetric L49.end L373 L439.start
  constraint symmetric L50.end L373 L494.end
  constraint symmetric L53.end L373 L404.end
  constraint symmetric L54.end L373 L425.start
  constraint symmetric L55.end L373 L441.end
  constraint symmetric L57.end L373 L425.end
  constraint symmetric L58.end L373 L404.start
  constraint symmetric L61.end L373 L415.end
  constraint symmetric L62.end L373 L419.start
  constraint symmetric L63.end L373 L481.start
  constraint symmetric L65.end L373 L403.start
  constraint symmetric L66.end L373 L403.end
  constraint symmetric L67.end L373 L502.start
  constraint symmetric L69.end L373 L407.end
  constraint symmetric L70.end L373 L407.start
  constraint symmetric L71.end L373 L415.start
  constraint symmetric L77.end L373 L395.start
  constraint symmetric L78.end L373 L375.end
  constraint symmetric L81.end L373 L380.start
  constraint symmetric L82.end L373 L377.end
  constraint symmetric L85.end L373 L416.start
  constraint symmetric L86.end L373 L377.start
  constraint symmetric L89.end L373 L427.start
  constraint symmetric L90.end L373 L382.end
  constraint symmetric L94.end L373 L375.start
  constraint symmetric L98.end L373 L384.end
  constraint symmetric L102.end L373 L400.end
  constraint symmetric L106.end L373 L379.end
  constraint symmetric L110.end L373 L376.end
  constraint symmetric L114.end L373 L376.start
  constraint symmetric L118.end L373 L382.start
  constraint symmetric L122.end L373 L391.end
  constraint symmetric L125.end L373 L399.start
  constraint symmetric L126.end L373 L389.start
  constraint symmetric L129.end L373 L422.end
  constraint symmetric L130.end L373 L374.end
  constraint symmetric L131.end L373 L374.start
  constraint symmetric L134.end L373 L383.start
  constraint symmetric L135.end L373 L390.start
  constraint symmetric L137.end L373 L378.start
  constraint symmetric L138.end L373 L378.end
  constraint symmetric L139.end L373 L396.start
  constraint symmetric L142.end L373 L388.start
  constraint symmetric L143.end L373 L388.end
  constraint symmetric L146.end L373 L381.start
  constraint symmetric L147.end L373 L381.end
  constraint symmetric L149.end L373 L386.end
  constraint symmetric L150.end L373 L496.end
  constraint symmetric L151.end L373 L489.start
  constraint symmetric L153.end L373 P0
  constraint symmetric L154.end L373 L639.end
  constraint symmetric L157.end L373 L603.start
  constraint symmetric L158.end L373 L603.end
  constraint symmetric L159.end L373 L572.end
  constraint symmetric L162.end L373 L604.end
  constraint symmetric L163.end L373 L572.start
  constraint symmetric L165.end L373 L600.start
  constraint symmetric L166.end L373 L535.end
  constraint symmetric L167.end L373 L535.start
  constraint symmetric L170.end L373 L545.end
  constraint symmetric L171.end L373 L545.start
  constraint symmetric L174.end L373 L544.start
  constraint symmetric L175.end L373 L544.end
  constraint symmetric L177.end L373 L599.end
  constraint symmetric L178.end L373 L524.start
  constraint symmetric L179.end L373 L526.end
  constraint symmetric L182.end L373 L524.end
  constraint symmetric L183.end L373 L526.start
  constraint symmetric L186.end L373 L527.end
  constraint symmetric L187.end L373 L527.start
  constraint symmetric L190.end L373 L539.end
  constraint symmetric L191.end L373 L537.start
  constraint symmetric L194.end L373 L547.end
  constraint symmetric L195.end L373 L588.end
  constraint symmetric L197.end L373 L543.end
  constraint symmetric L198.end L373 L547.start
  constraint symmetric L202.end L373 L522.start
  constraint symmetric L203.end L373 L541.start
  constraint symmetric L206.end L373 L522.end
  constraint symmetric L207.end L373 L570.start
  constraint symmetric L210.end L373 L574.start
  constraint symmetric L211.end L373 L546.end
  constraint symmetric L214.end L373 L556.start
  constraint symmetric L215.end L373 L546.start
  constraint symmetric L218.end L373 L586.end
  constraint symmetric L219.end L373 L585.start
  constraint symmetric L222.end L373 L532.end
  constraint symmetric L223.end L373 L533.end
  constraint symmetric L226.end L373 L532.start
  constraint symmetric L227.end L373 L533.start
  constraint symmetric L229.end L373 L528.start
  constraint symmetric L230.end L373 L528.end
  constraint symmetric L234.end L373 L552.end
  constraint symmetric L235.end L373 L530.end
  constraint symmetric L238.end L373 L536.end
  constraint symmetric L239.end L373 L529.end
  constraint symmetric L242.end L373 L538.end
  constraint symmetric L243.end L373 L529.start
  constraint symmetric L246.end L373 L531.end
  constraint symmetric L247.end L373 L531.start
  constraint symmetric L250.end L373 L563.end
  constraint symmetric L251.end L373 L554.start
  constraint symmetric L253.end L373 L560.start
  constraint symmetric L254.end L373 L560.end
  constraint symmetric L258.end L373 L636.end
  constraint symmetric L259.end L373 L646.end
  constraint symmetric L262.end L373 L628.end
  constraint symmetric L263.end L373 L628.start
  constraint symmetric L266.end L373 L640.start
  constraint symmetric L267.end L373 L611.end
  constraint symmetric L269.end L373 L627.start
  constraint symmetric L270.end L373 L611.start
  constraint symmetric L274.end L373 L625.end
  constraint symmetric L275.end L373 L617.start
  constraint symmetric L277.start L373 L645.start
  constraint symmetric L279.end L373 L632.end
  constraint symmetric L282.end L373 L629.end
  constraint symmetric L283.end L373 L641.end
  constraint symmetric L285.end L373 L631.end
  constraint symmetric L286.end L373 L626.end
  constraint symmetric L287.end L373 L641.start
  constraint symmetric L289.end L373 L523.start
  constraint symmetric L290.end L373 L525.end
  constraint symmetric L293.end L373 L523.end
  constraint symmetric L294.end L373 L525.start
  constraint symmetric L297.end L373 L584.end
  constraint symmetric L298.end L373 P1
  constraint symmetric L309.start L373 L667.start
  constraint symmetric L309.end L373 L667.end
  constraint symmetric L313.end L373 L671.end
  constraint symmetric L317.end L373 L676.start
  constraint symmetric L318.end L373 L666.start
  constraint symmetric L319.end L373 L666.end
  constraint symmetric L321.end L373 L668.end
  constraint symmetric L322.end L373 L679.end
  constraint symmetric L323.end L373 L678.start
  constraint symmetric L346.end L373 L672.start
  constraint symmetric L349.end L373 L672.end
  constraint symmetric L350.end L373 L669.start
  constraint symmetric L342.end L373 L669.end
  constraint symmetric L354.end L373 L675.start
  constraint symmetric L355.end L373 L687.end
  constraint symmetric L357.end L373 L670.end
  constraint symmetric L358.end L373 L682.start
  constraint symmetric L361.end L373 L686.end
  constraint symmetric L362.end L373 L674.start
  constraint symmetric L363.end L373 L670.start
  constraint symmetric L365.end L373 L664.start
  constraint symmetric L366.end L373 L664.end
  constraint symmetric L367.end L373 L689.start
  constraint symmetric L301.end L373 L698.start
  constraint symmetric L302.end L373 L695.start
  constraint symmetric L305.end L373 L698.end
  constraint symmetric L306.end L373 L719.start
  constraint symmetric L314.end L373 L728.end
  constraint symmetric L326.end L373 L717.start
  constraint symmetric L327.end L373 L702.end
  constraint symmetric L329.end L373 L720.end
  constraint symmetric L330.end L373 L721.start
  constraint symmetric L334.end L373 L744.start
  constraint symmetric L335.end L373 L710.end
  constraint symmetric L337.end L373 L714.end
  constraint symmetric L338.end L373 L734.start
  constraint symmetric L339.end L373 L710.start
  constraint symmetric L343.end L373 L709.start
  constraint symmetric L347.end L373 L726.start
  constraint symmetric L369.end L373 L692.start
  constraint symmetric L370.end L373 L692.end
  constraint coincident P0 L767.start
  constraint perpendicular L639 L770
  constraint perpendicular L517 L772
  constraint perpendicular L12 L773
  constraint perpendicular L6 L774
  measures "d1" distance of L0.start L2.end
  measures "d2" distance of L0.start L0.end
  measures "d3" distance of L4.start L5.end
extrude "Extrude1" add sketch "Sketch2" along normal blind 2 makes body 1
extrude "Extrude2" add 1 faces at (335, 294, 2) along direction (0, 0, 1) blind 6 thin wall 1 inside on bodies 1 bodies 1
delete_face "DeleteFace1" 1 faces at (407, 290.5, 4) on bodies 1
copy_body "CopyPasteBodies1" bodies 1 makes body 2
move_body "Move1" bodies 2 to x (1, 0, 0) y (0, 1, 0) z (0, 0, 1) at (-3.0599, -124.4354, 0)